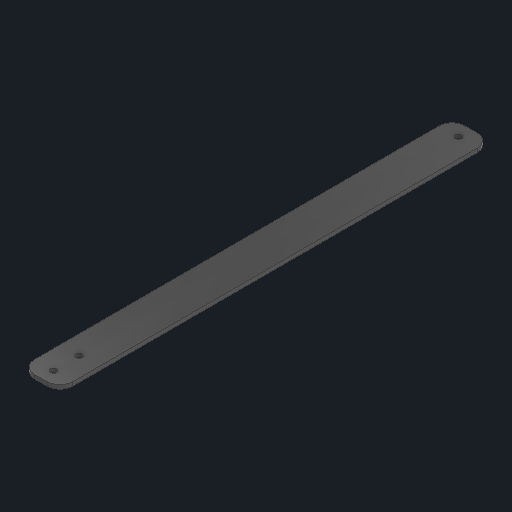
# Autodesk Inventor part: DragChainSupport
Saved by Autodesk Inventor 2027.1 (Build 311270010, 270A)
## iProperties
Created: 2026-10-20
Part Number: DragChainSupport
Material: MDF Medium Density Fiberboard
Document SubType Name: Modeling
Designer: SDS Scholar
Density: 0.8 g/cm^3
Appearance: Cardboard - Corrugated
Author: SDS Scholar
Autodesk Inventor part; units mm, degrees
ref_plane "YZ Plane" through (0, 0, 0) normal (1, 0, 0) x (0, 1, 0)
ref_plane "XZ Plane" through (0, 0, 0) normal (0, 1, 0) x (-1, 0, 0)
ref_plane "XY Plane" through (0, 0, 0) normal (0, 0, 1) x (1, 0, 0)
sketch "Sketch1" plane through (0, 0, 0) normal (0, 1, 0) x (-1, 0, 0)
  line L0 (15, 168.5) -> (-15, 168.5)
  line L1 (-15, 168.5) -> (-15, -168.5)
  line L2 (-15, -168.5) -> (15, -168.5)
  line L3 (15, -168.5) -> (15, 168.5)
  circle A0 centre (0, 158.5) radius 2.5
  line L4 (15, 0) -> (-15, 0) construction
  circle A1 centre (0, -158.5) radius 2.5
  circle A2 centre (0, 138.5) radius 2.5
  point P0 (0, 0)
  point P1 (0, -168.5)
  point P2 (0, 0)
  dimension "d0" = 30
  dimension "d1" = 337
  dimension "d2" = 5
  dimension "d3" = 158.5
  dimension "d7" = 5
  dimension "d8" = 20
  constraints: 10 end point, 4 midpoint, 3 centre point, 3 vertical alignment, 2 parallel, 1 horizontal, 1 horizontal alignment, 1 perpendicular, 1 symmetric about line, 1 other
  measures "d0" distance of L1.end L2.end
  measures "d1" distance of L0.end L1.end
  measures "d2" diameter of A0
  measures "d3" distance of point (0, 0) A0.centre
  measures "d7" diameter of A2
  measures "d8" distance of A0.centre A2.centre
extrude "Extrusion1" add sketch "Sketch1" along normal blind 3
fillet "Fillet1" radius 10 4 edges at (15, 1.5, 168.5) (-15, 1.5, 168.5) (15, 1.5, -168.5) (-15, 1.5, -168.5)
equation "\"d1\" = WorkspaceWidth - 4 * AluminiumExtrusionBase"
equation "\"GridProcutClearance\" = 3"
equation "\"GridBorderThickness\" = 5"
equation "\"GridBorderFillets\" = 7"
equation "\"GridTotalSize\" = 63"
equation "\"BaseTotalWidth\" = 652"
equation "\"BaseTotalLength\" = 912"
equation "\"DistanceBetweenGrid\" = 5"
equation "\"WorkspaceLength\" = 552"
equation "\"WorkspaceWidth\" = 417"
equation "\"WorkspaceHeight\" = 146.5"
equation "\"AxesBaseFillet\" = 15"
equation "\"Zaxis\" = 223"
equation "\"ProductTotalHeight\" = 45"
equation "\"VerticalStroke\" = 105"
equation "\"CylinderStroke\" = 75"
equation "\"BaseWoodThickness\" = 7"
equation "\"Kerf\" = 0.3"
equation "\"RxThickness\" = 1.8"
equation "\"AluminiumExtrusionBase\" = 20"
body "Solid1"
